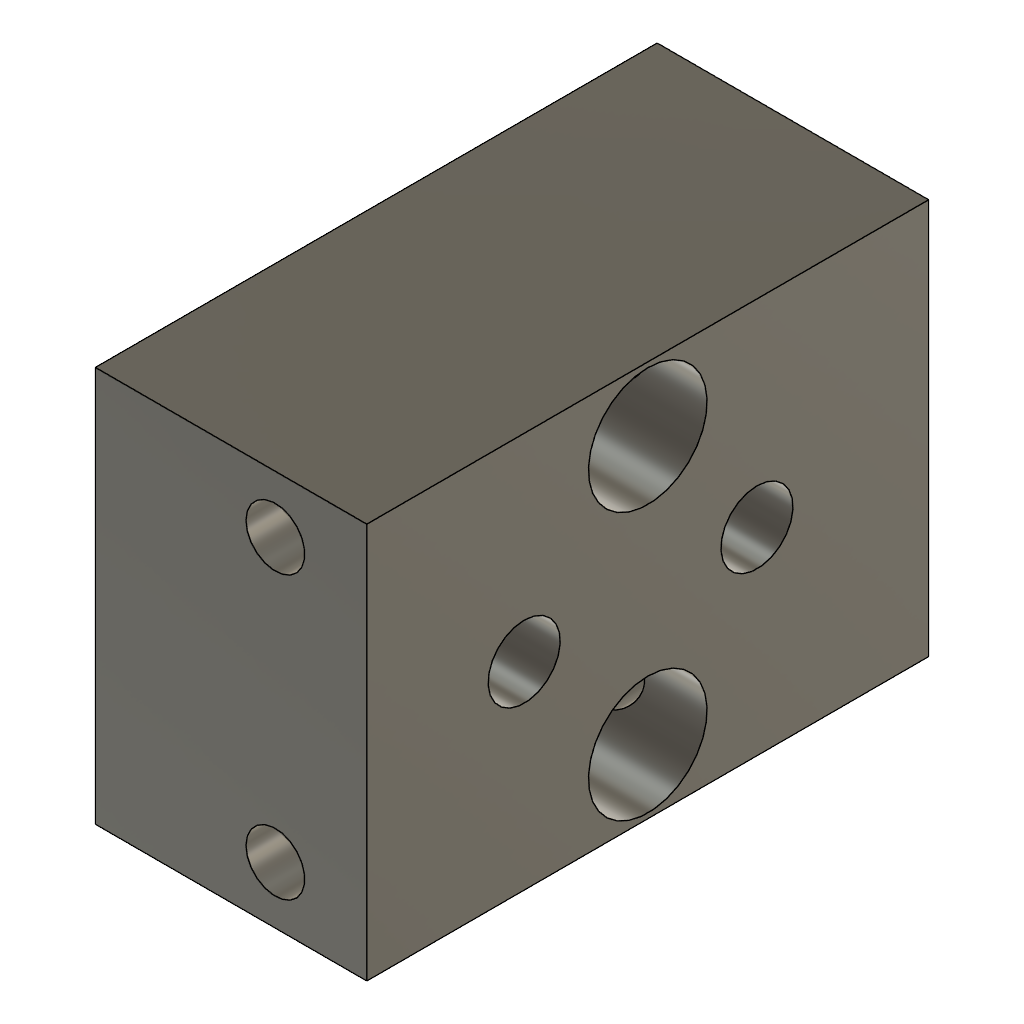
tab-saddle (Autodesk Fusion 360 design; units mm, degrees)
part number: 2026-11-19-10-54-52-134
Autodesk Fusion 360 part; units mm, degrees
sketch "Width and captured tab height" plane through (0, 0, 0) normal (0, 0, 1) x (1, 0, 0)
  line L0 (0, 0) -> (24.5, 0)
  line L1 (24.5, 0) -> (24.5, 50.7)
  line L2 (24.5, 50.7) -> (0, 50.7)
  line L3 (0, 50.7) -> (0, 0)
  dimension "d7" = 24.5
  dimension "d8" = 50.7
  measures "d7" horizontal distance of L0.start L0.end
  measures "d8" vertical distance of L0.end L1.end
extrude "Mill full stock" add sketch "Width and captured tab height" along normal blind 35.7
sketch "Fixture-drill both tab through holes" plane through (0, 0, 0) normal (0, 1, 0) x (1, 0, 0)
  circle A0 centre (16.25, -5.15) radius 2.65
  circle A1 centre (16.25, -30.55) radius 2.65
  dimension "d11" = 5.3
  dimension "d12" = 5.3
  measures "d11" diameter of A0
  measures "d12" diameter of A1
extrude "Fixture-drill both tab through holes (1)" cut sketch "Fixture-drill both tab through holes" along normal mid plane 200
sketch "Cross-drill frame screws" plane through (0, 0, 0) normal (1, 0, 0) x (0, 0, -1)
  circle A0 centre (-17.85, 14.2) radius 3.25
  circle A1 centre (-17.85, 35.2) radius 3.25
  dimension "d15" = 6.5
  dimension "d16" = 6.5
  measures "d15" diameter of A0
  measures "d16" diameter of A1
extrude "Cross-drill frame screws (1)" cut sketch "Cross-drill frame screws" along normal mid plane 200
sketch "Relieve the two webs" plane through (0, 0, 0) normal (1, 0, 0) x (0, 0, -1)
  circle A0 centre (-5.8, 25.35) radius 5.35
  circle A1 centre (-29.9, 25.35) radius 5.35
  dimension "d19" = 10.7
  dimension "d20" = 10.7
  measures "d19" diameter of A0
  measures "d20" diameter of A1
extrude "Relieve the two webs (1)" cut sketch "Relieve the two webs" along normal mid plane 200
equation "SaddleWidth = 24.5 mm" comment "Finished saddle dimension"
equation "SaddleHeight = 50.7 mm" comment "Finished saddle dimension"
equation "SaddleLength = 35.7 mm" comment "Finished saddle dimension"
equation "TabBore = 5.3 mm" comment "Finished saddle dimension"
equation "FrameBore = 6.5 mm" comment "Finished saddle dimension"
equation "LighteningBore = 10.7 mm" comment "Finished saddle dimension"
equation "d7 = SaddleWidth"
equation "d8 = SaddleHeight"
equation "d9 = SaddleLength"
equation "d11 = TabBore"
equation "d12 = TabBore"
equation "d15 = FrameBore"
equation "d16 = FrameBore"
equation "d19 = LighteningBore"
equation "d20 = LighteningBore"
named bodies: "Tab saddle"
